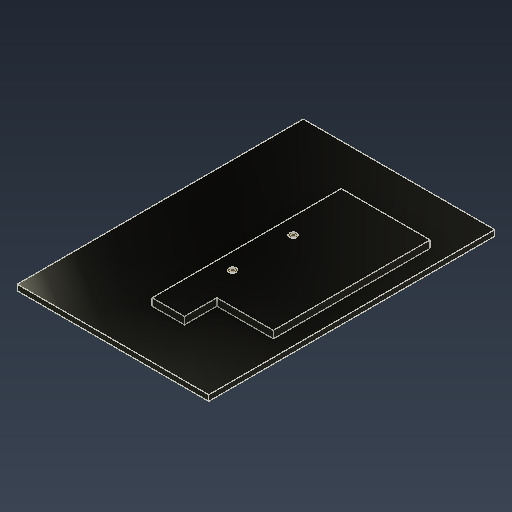
# Autodesk Inventor part: 16inch capacitive display
Saved by Autodesk Inventor 2026.2 (Build 302298010, 298A)
## iProperties
Created: 2026-05-13
Part Number: 16inch capacitive display
Material: ABS 플라스틱
Document SubType Name: Modeling
Designer: khw
Density: 1.06 g/cm^3
Appearance: 암회색
Author: khw
Autodesk Inventor part; units mm, degrees
ref_plane "YZ Plane" through (0, 0, 0) normal (1, 0, 0) x (0, 1, 0)
ref_plane "XZ Plane" through (0, 0, 0) normal (0, 1, 0) x (-1, 0, 0)
ref_plane "XY Plane" through (0, 0, 0) normal (0, 0, 1) x (1, 0, 0)
sketch "스케치1" plane through (0, 0, 0) normal (0, 1, 0) x (-1, 0, 0)
  line L0 (-118.5, 177) -> (118.5, 177)
  line L1 (118.5, 177) -> (118.5, -177)
  line L2 (118.5, -177) -> (-118.5, -177)
  line L3 (-118.5, -177) -> (-118.5, 177)
  line L4 (-118.5, 177) -> (118.5, -177) construction
  line L5 (118.5, 177) -> (-118.5, -177) construction
  line L6 (110.5, 169) -> (-88.5, 169)
  line L7 (-88.5, 169) -> (-88.5, -169)
  line L8 (-88.5, -169) -> (110.5, -169)
  line L9 (110.5, -169) -> (110.5, 169)
  line L10 (118.5, 0) -> (-118.5, 0) construction
  point P0 (0, 0)
  point P1 (110.5, 0)
  dimension "d0" = 237
  dimension "d1" = 354
  dimension "d2" = 8
  dimension "d3" = 8
  dimension "d4" = 30
  constraints: 22 end point, 5 midpoint, 4 parallel, 2 horizontal, 2 perpendicular, 1 point on line
  measures "d0" distance of L1.end L2.end
  measures "d1" distance of L0.end L1.end
  measures "d2" distance between parallel lines of L1 L9
  measures "d3" distance between parallel lines of L0 L6
  measures "d4" distance between parallel lines of L3 L7
extrude "돌출1" add sketch "스케치1" along normal blind 7 contours L0 L1 L2 L3 | L9 L8 L7 L6
extrude "돌출2" cut sketch "스케치1" along normal blind 0.2 contours L9 L8 L7 L6
sketch "스케치2" plane through (0, 7, 0) normal (0, 1, 0) x (1, 0, 0)
  line L0 (-11.5, -117) -> (98.5, -117)
  line L1 (98.5, -117) -> (98.5, 117)
  line L2 (98.5, 117) -> (-11.5, 117)
  line L3 (-11.5, 117) -> (-11.5, -117)
  line L4 (28.5, -117) -> (98.5, -117)
  line L5 (98.5, -117) -> (98.5, -77)
  line L6 (98.5, -77) -> (28.5, -77)
  line L7 (28.5, -77) -> (28.5, -117)
  line L8 (118.5, 177) -> (-118.5, 177) projected
  line L9 (-118.5, 177) -> (-118.5, -177) projected
  line L10 (-118.5, -177) -> (118.5, -177) projected
  line L11 (118.5, -177) -> (118.5, 177) projected
  line L12 (-118.5, 0) -> (118.5, 0) construction
  point P0 (0, 0)
  point P1 (-11.5, 0)
  point P2 (63.5, -117)
  dimension "d9" = 60
  dimension "d10" = 130
  dimension "d11" = 20
  dimension "d12" = 40
  dimension "d13" = 40
  constraints: 18 end point, 4 midpoint, 4 parallel, 3 point on line, 2 horizontal, 2 perpendicular
  measures "d9" distance between parallel lines of L10 L0
  measures "d10" distance between parallel lines of L11 L3
  measures "d11" distance between parallel lines of L11 L1
  measures "d12" distance between parallel lines of L3 L7
  measures "d13" distance from line of point (63.5, -117) L6
extrude "돌출3" add sketch "스케치2" along normal blind 9 contours L3 L2 L1 L6 L7 L0
sketch "스케치3" plane through (0, 16, 0) normal (0, 1, 0) x (1, 0, 0)
  line L0 (-11.5, -117) -> (-11.5, 117) projected
  line L1 (-11.5, 0) -> (97.0232, 0) construction
  line L2 (8.5, -37.5) -> (8.5, 37.5) construction
  circle A0 centre (8.5, -37.5) radius 2.5
  circle A1 centre (8.5, 37.5) radius 2.5
  point P0 (0, 0)
  point P1 (8.5, 0)
  dimension "d16" = 75
  dimension "d17" = 20
  dimension "d18" = 5
  dimension "d19" = 5
  constraints: 4 end point, 2 centre point, 2 coincident, 2 midpoint, 1 horizontal, 1 point on line, 1 vertical
  measures "d16" distance of L2.start L2.end
  measures "d17" distance between parallel lines of L0 L2
  measures "d18" diameter of A0
  measures "d19" diameter of A1
extrude "돌출4" cut sketch "스케치3" against normal blind 5
sketch "스케치4" plane through (0, 16, 0) normal (0, 1, 0) x (1, 0, 0)
  circle A0 centre (8.5, 37.5) radius 2.5 projected
  circle A1 centre (8.5, -37.5) radius 2.5 projected
  line L0 (-11.5, -117) -> (28.5, -117) projected
  line L1 (28.5, -117) -> (28.5, -77) projected
  line L2 (28.5, -77) -> (98.5, -77) projected
  line L3 (98.5, -77) -> (98.5, 117) projected
  line L4 (98.5, 117) -> (-11.5, 117) projected
  line L5 (-11.5, 117) -> (-11.5, -117) projected
  circle A2 centre (8.5, -37.5) radius 4.5
  circle A3 centre (8.5, 37.5) radius 4.5
  point P0 (0, 0)
  dimension "d22" = 2
  dimension "d23" = 2
  constraints: 2 centre point, 2 coincident
  measures "d22" radial gap between concentric circles of A0 A3
  measures "d23" radial gap between concentric circles of A2 A1
extrude "돌출5" cut sketch "스케치4" against normal blind 0.2 contours A2 | A3
thread "스레드1" size "M5x0.8" class "6H" standard "ISO Metric profile" full length
thread "스레드2" size "M5x0.8" class "6H" standard "ISO Metric profile" full length
